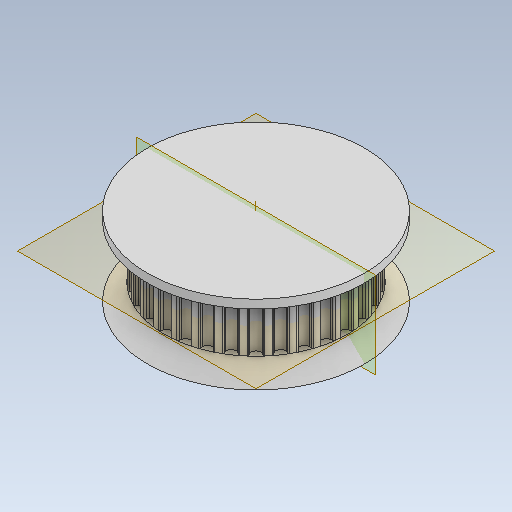
# Autodesk Inventor part: Riemenscheibe  GT2 32 Zähne mit kegel
Saved by Autodesk Inventor 2026.4 (Build 304435030, 435C)
## iProperties
Created: 2026-11-11
Part Number: Riemenscheibe  GT2 32 Zähne mit kegel
Material: Generisch
Document SubType Name: Modeling
Designer: weira
Density: 1 g/cm^3
Appearance: Vorgabe
Author: weira
Autodesk Inventor part; units mm, degrees
ref_plane "YZ Plane" through (0, 0, 0) normal (1, 0, 0) x (0, 1, 0)
sketch "Skizze1" plane through (0, 0, 0) normal (0, 0, 1) x (1, 0, 0)
  circle A0 centre (0, 0) radius 9.93
  arc A1 (-0.5239, 10.2923) -> (0.5239, 10.2923) centre (0, 10.49) ccw
  circle A2 centre (0, 0) radius 10.68
  arc A3 (0.4927, 10.2239) -> (0.5889, 10.5298) centre (-0.4, 10.6725) ccw
  arc A4 (-0.5889, 10.5298) -> (-0.5239, 10.2923) centre (0.4, 10.6725) ccw
  arc A5 (-0.5889, 10.5298) -> (-0.7421, 10.6542) centre (-0.7367, 10.5043) ccw
  line L0 (0, 10.49) -> (0, 10.844)
  arc A6 (0.7421, 10.6542) -> (0.5889, 10.5298) centre (0.7367, 10.5043) ccw
  arc A7 (-2.5218, 9.9923) -> (-1.4941, 10.1967) centre (-2.0465, 10.2884) ccw
  arc A8 (-1.5113, 10.1235) -> (-1.4767, 10.4423) centre (-2.4744, 10.3894) ccw
  arc A9 (-2.6318, 10.2126) -> (-2.5218, 9.9923) centre (-1.6898, 10.5455) ccw
  arc A10 (-2.6318, 10.2126) -> (-2.8064, 10.3047) centre (-2.7718, 10.1587) ccw
  arc A11 (-1.3507, 10.5942) -> (-1.4767, 10.4423) centre (-1.3268, 10.4462) ccw
  line L1 (-2.0465, 10.2884) -> (-2.1156, 10.6356)
  arc A12 (-4.4227, 9.3083) -> (-3.4546, 9.7093) centre (-4.0143, 9.6915) ccw
  arc A13 (-3.4573, 9.6342) -> (-3.4855, 9.9536) centre (-4.4537, 9.707) ccw
  arc A14 (-4.5736, 9.5029) -> (-4.4227, 9.3083) centre (-3.7146, 10.0132) ccw
  arc A15 (-4.5736, 9.5029) -> (-4.7628, 9.5592) centre (-4.7004, 9.4228) ccw
  arc A16 (-3.3916, 10.1272) -> (-3.4855, 9.9536) centre (-3.3392, 9.9866) ccw
  line L2 (-4.0143, 9.6915) -> (-4.1498, 10.0185)
  arc A17 (-6.1537, 8.2666) -> (-5.2824, 8.8488) centre (-5.8279, 8.7221) ccw
  arc A18 (-5.2704, 8.7746) -> (-5.3604, 9.0823) centre (-6.2619, 8.6516) ccw
  arc A19 (-6.3397, 8.428) -> (-6.1537, 8.2666) centre (-5.5967, 9.0961) ccw
  arc A20 (-6.3397, 8.428) -> (-6.5362, 8.4463) centre (-6.4484, 8.3247) ccw
  arc A21 (-5.3021, 9.2709) -> (-5.3604, 9.0823) centre (-5.2233, 9.1433) ccw
  line L3 (-5.8279, 8.7221) -> (-6.0246, 9.0164)
  arc A22 (-7.6482, 6.9073) -> (-6.9073, 7.6482) centre (-7.4176, 7.4176) ccw
  arc A23 (-6.881, 7.5778) -> (-7.0293, 7.8621) centre (-7.8294, 7.2638) ccw
  arc A24 (-7.8621, 7.0293) -> (-7.6482, 6.9073) centre (-7.2638, 7.8294) ccw
  arc A25 (-7.8621, 7.0293) -> (-8.0584, 7.0089) centre (-7.9486, 6.9067) ccw
  arc A26 (-7.0089, 8.0584) -> (-7.0293, 7.8621) centre (-6.9067, 7.9486) ccw
  line L4 (-7.4176, 7.4176) -> (-7.6678, 7.6678)
  arc A27 (-8.8488, 5.2824) -> (-8.2666, 6.1537) centre (-8.7221, 5.8279) ccw
  arc A28 (-8.2271, 6.0897) -> (-8.428, 6.3397) centre (-9.0961, 5.5967) ccw
  arc A29 (-9.0823, 5.3604) -> (-8.8488, 5.2824) centre (-8.6516, 6.2619) ccw
  arc A30 (-9.0823, 5.3604) -> (-9.2709, 5.3021) centre (-9.1433, 5.2233) ccw
  arc A31 (-8.4463, 6.5362) -> (-8.428, 6.3397) centre (-8.3247, 6.4484) ccw
  line L5 (-8.7221, 5.8279) -> (-9.0164, 6.0246)
  arc A32 (-9.7093, 3.4546) -> (-9.3083, 4.4227) centre (-9.6915, 4.0143) ccw
  arc A33 (-9.2571, 4.3677) -> (-9.5029, 4.5736) centre (-10.0132, 3.7146) ccw
  arc A34 (-9.9536, 3.4855) -> (-9.7093, 3.4546) centre (-9.707, 4.4537) ccw
  arc A35 (-9.9536, 3.4855) -> (-10.1272, 3.3916) centre (-9.9866, 3.3392) ccw
  arc A36 (-9.5592, 4.7628) -> (-9.5029, 4.5736) centre (-9.4228, 4.7004) ccw
  line L6 (-9.6915, 4.0143) -> (-10.0185, 4.1498)
  arc A37 (-10.1967, 1.4941) -> (-9.9923, 2.5218) centre (-10.2884, 2.0465) ccw
  arc A38 (-9.9313, 2.4778) -> (-10.2126, 2.6318) centre (-10.5455, 1.6898) ccw
  arc A39 (-10.4423, 1.4767) -> (-10.1967, 1.4941) centre (-10.3894, 2.4744) ccw
  arc A40 (-10.4423, 1.4767) -> (-10.5942, 1.3507) centre (-10.4462, 1.3268) ccw
  arc A41 (-10.3047, 2.8064) -> (-10.2126, 2.6318) centre (-10.1587, 2.7718) ccw
  line L7 (-10.2884, 2.0465) -> (-10.6356, 2.1156)
  arc A42 (-10.2923, -0.5239) -> (-10.2923, 0.5239) centre (-10.49, 0) ccw
  arc A43 (-10.2239, 0.4927) -> (-10.5298, 0.5889) centre (-10.6725, -0.4) ccw
  arc A44 (-10.5298, -0.5889) -> (-10.2923, -0.5239) centre (-10.6725, 0.4) ccw
  arc A45 (-10.5298, -0.5889) -> (-10.6542, -0.7421) centre (-10.5043, -0.7367) ccw
  arc A46 (-10.6542, 0.7421) -> (-10.5298, 0.5889) centre (-10.5043, 0.7367) ccw
  line L8 (-10.49, 0) -> (-10.844, 0)
  arc A47 (-9.9923, -2.5218) -> (-10.1967, -1.4941) centre (-10.2884, -2.0465) ccw
  arc A48 (-10.1235, -1.5113) -> (-10.4423, -1.4767) centre (-10.3894, -2.4744) ccw
  arc A49 (-10.2126, -2.6318) -> (-9.9923, -2.5218) centre (-10.5455, -1.6898) ccw
  arc A50 (-10.2126, -2.6318) -> (-10.3047, -2.8064) centre (-10.1587, -2.7718) ccw
  arc A51 (-10.5942, -1.3507) -> (-10.4423, -1.4767) centre (-10.4462, -1.3268) ccw
  line L9 (-10.2884, -2.0465) -> (-10.6356, -2.1156)
  arc A52 (-9.3083, -4.4227) -> (-9.7093, -3.4546) centre (-9.6915, -4.0143) ccw
  arc A53 (-9.6342, -3.4573) -> (-9.9536, -3.4855) centre (-9.707, -4.4537) ccw
  arc A54 (-9.5029, -4.5736) -> (-9.3083, -4.4227) centre (-10.0132, -3.7146) ccw
  arc A55 (-9.5029, -4.5736) -> (-9.5592, -4.7628) centre (-9.4228, -4.7004) ccw
  arc A56 (-10.1272, -3.3916) -> (-9.9536, -3.4855) centre (-9.9866, -3.3392) ccw
  line L10 (-9.6915, -4.0143) -> (-10.0185, -4.1498)
  arc A57 (-8.2666, -6.1537) -> (-8.8488, -5.2824) centre (-8.7221, -5.8279) ccw
  arc A58 (-8.7746, -5.2704) -> (-9.0823, -5.3604) centre (-8.6516, -6.2619) ccw
  arc A59 (-8.428, -6.3397) -> (-8.2666, -6.1537) centre (-9.0961, -5.5967) ccw
  arc A60 (-8.428, -6.3397) -> (-8.4463, -6.5362) centre (-8.3247, -6.4484) ccw
  arc A61 (-9.2709, -5.3021) -> (-9.0823, -5.3604) centre (-9.1433, -5.2233) ccw
  line L11 (-8.7221, -5.8279) -> (-9.0164, -6.0246)
  arc A62 (-6.9073, -7.6482) -> (-7.6482, -6.9073) centre (-7.4176, -7.4176) ccw
  arc A63 (-7.5778, -6.881) -> (-7.8621, -7.0293) centre (-7.2638, -7.8294) ccw
  arc A64 (-7.0293, -7.8621) -> (-6.9073, -7.6482) centre (-7.8294, -7.2638) ccw
  arc A65 (-7.0293, -7.8621) -> (-7.0089, -8.0584) centre (-6.9067, -7.9486) ccw
  arc A66 (-8.0584, -7.0089) -> (-7.8621, -7.0293) centre (-7.9486, -6.9067) ccw
  line L12 (-7.4176, -7.4176) -> (-7.6678, -7.6678)
  arc A67 (-5.2824, -8.8488) -> (-6.1537, -8.2666) centre (-5.8279, -8.7221) ccw
  arc A68 (-6.0897, -8.2271) -> (-6.3397, -8.428) centre (-5.5967, -9.0961) ccw
  arc A69 (-5.3604, -9.0823) -> (-5.2824, -8.8488) centre (-6.2619, -8.6516) ccw
  arc A70 (-5.3604, -9.0823) -> (-5.3021, -9.2709) centre (-5.2233, -9.1433) ccw
  arc A71 (-6.5362, -8.4463) -> (-6.3397, -8.428) centre (-6.4484, -8.3247) ccw
  line L13 (-5.8279, -8.7221) -> (-6.0246, -9.0164)
  arc A72 (-3.4546, -9.7093) -> (-4.4227, -9.3083) centre (-4.0143, -9.6915) ccw
  arc A73 (-4.3677, -9.2571) -> (-4.5736, -9.5029) centre (-3.7146, -10.0132) ccw
  arc A74 (-3.4855, -9.9536) -> (-3.4546, -9.7093) centre (-4.4537, -9.707) ccw
  arc A75 (-3.4855, -9.9536) -> (-3.3916, -10.1272) centre (-3.3392, -9.9866) ccw
  arc A76 (-4.7628, -9.5592) -> (-4.5736, -9.5029) centre (-4.7004, -9.4228) ccw
  line L14 (-4.0143, -9.6915) -> (-4.1498, -10.0185)
  arc A77 (-1.4941, -10.1967) -> (-2.5218, -9.9923) centre (-2.0465, -10.2884) ccw
  arc A78 (-2.4778, -9.9313) -> (-2.6318, -10.2126) centre (-1.6898, -10.5455) ccw
  arc A79 (-1.4767, -10.4423) -> (-1.4941, -10.1967) centre (-2.4744, -10.3894) ccw
  arc A80 (-1.4767, -10.4423) -> (-1.3507, -10.5942) centre (-1.3268, -10.4462) ccw
  arc A81 (-2.8064, -10.3047) -> (-2.6318, -10.2126) centre (-2.7718, -10.1587) ccw
  line L15 (-2.0465, -10.2884) -> (-2.1156, -10.6356)
  arc A82 (0.5239, -10.2923) -> (-0.5239, -10.2923) centre (0, -10.49) ccw
  arc A83 (-0.4927, -10.2239) -> (-0.5889, -10.5298) centre (0.4, -10.6725) ccw
  arc A84 (0.5889, -10.5298) -> (0.5239, -10.2923) centre (-0.4, -10.6725) ccw
  arc A85 (0.5889, -10.5298) -> (0.7421, -10.6542) centre (0.7367, -10.5043) ccw
  arc A86 (-0.7421, -10.6542) -> (-0.5889, -10.5298) centre (-0.7367, -10.5043) ccw
  line L16 (0, -10.49) -> (0, -10.844)
  arc A87 (2.5218, -9.9923) -> (1.4941, -10.1967) centre (2.0465, -10.2884) ccw
  arc A88 (1.5113, -10.1235) -> (1.4767, -10.4423) centre (2.4744, -10.3894) ccw
  arc A89 (2.6318, -10.2126) -> (2.5218, -9.9923) centre (1.6898, -10.5455) ccw
  arc A90 (2.6318, -10.2126) -> (2.8064, -10.3047) centre (2.7718, -10.1587) ccw
  arc A91 (1.3507, -10.5942) -> (1.4767, -10.4423) centre (1.3268, -10.4462) ccw
  line L17 (2.0465, -10.2884) -> (2.1156, -10.6356)
  arc A92 (4.4227, -9.3083) -> (3.4546, -9.7093) centre (4.0143, -9.6915) ccw
  arc A93 (3.4573, -9.6342) -> (3.4855, -9.9536) centre (4.4537, -9.707) ccw
  arc A94 (4.5736, -9.5029) -> (4.4227, -9.3083) centre (3.7146, -10.0132) ccw
  arc A95 (4.5736, -9.5029) -> (4.7628, -9.5592) centre (4.7004, -9.4228) ccw
  arc A96 (3.3916, -10.1272) -> (3.4855, -9.9536) centre (3.3392, -9.9866) ccw
  line L18 (4.0143, -9.6915) -> (4.1498, -10.0185)
  arc A97 (6.1537, -8.2666) -> (5.2824, -8.8488) centre (5.8279, -8.7221) ccw
  arc A98 (5.2704, -8.7746) -> (5.3604, -9.0823) centre (6.2619, -8.6516) ccw
  arc A99 (6.3397, -8.428) -> (6.1537, -8.2666) centre (5.5967, -9.0961) ccw
  arc A100 (6.3397, -8.428) -> (6.5362, -8.4463) centre (6.4484, -8.3247) ccw
  arc A101 (5.3021, -9.2709) -> (5.3604, -9.0823) centre (5.2233, -9.1433) ccw
  line L19 (5.8279, -8.7221) -> (6.0246, -9.0164)
  arc A102 (7.6482, -6.9073) -> (6.9073, -7.6482) centre (7.4176, -7.4176) ccw
  arc A103 (6.881, -7.5778) -> (7.0293, -7.8621) centre (7.8294, -7.2638) ccw
  arc A104 (7.8621, -7.0293) -> (7.6482, -6.9073) centre (7.2638, -7.8294) ccw
  arc A105 (7.8621, -7.0293) -> (8.0584, -7.0089) centre (7.9486, -6.9067) ccw
  arc A106 (7.0089, -8.0584) -> (7.0293, -7.8621) centre (6.9067, -7.9486) ccw
  line L20 (7.4176, -7.4176) -> (7.6678, -7.6678)
  arc A107 (8.8488, -5.2824) -> (8.2666, -6.1537) centre (8.7221, -5.8279) ccw
  arc A108 (8.2271, -6.0897) -> (8.428, -6.3397) centre (9.0961, -5.5967) ccw
  arc A109 (9.0823, -5.3604) -> (8.8488, -5.2824) centre (8.6516, -6.2619) ccw
  arc A110 (9.0823, -5.3604) -> (9.2709, -5.3021) centre (9.1433, -5.2233) ccw
  arc A111 (8.4463, -6.5362) -> (8.428, -6.3397) centre (8.3247, -6.4484) ccw
  line L21 (8.7221, -5.8279) -> (9.0164, -6.0246)
  arc A112 (9.7093, -3.4546) -> (9.3083, -4.4227) centre (9.6915, -4.0143) ccw
  arc A113 (9.2571, -4.3677) -> (9.5029, -4.5736) centre (10.0132, -3.7146) ccw
  arc A114 (9.9536, -3.4855) -> (9.7093, -3.4546) centre (9.707, -4.4537) ccw
  arc A115 (9.9536, -3.4855) -> (10.1272, -3.3916) centre (9.9866, -3.3392) ccw
  arc A116 (9.5592, -4.7628) -> (9.5029, -4.5736) centre (9.4228, -4.7004) ccw
  line L22 (9.6915, -4.0143) -> (10.0185, -4.1498)
  arc A117 (10.1967, -1.4941) -> (9.9923, -2.5218) centre (10.2884, -2.0465) ccw
  arc A118 (9.9313, -2.4778) -> (10.2126, -2.6318) centre (10.5455, -1.6898) ccw
  arc A119 (10.4423, -1.4767) -> (10.1967, -1.4941) centre (10.3894, -2.4744) ccw
  arc A120 (10.4423, -1.4767) -> (10.5942, -1.3507) centre (10.4462, -1.3268) ccw
  arc A121 (10.3047, -2.8064) -> (10.2126, -2.6318) centre (10.1587, -2.7718) ccw
  line L23 (10.2884, -2.0465) -> (10.6356, -2.1156)
  arc A122 (10.2923, 0.5239) -> (10.2923, -0.5239) centre (10.49, 0) ccw
  arc A123 (10.2239, -0.4927) -> (10.5298, -0.5889) centre (10.6725, 0.4) ccw
  arc A124 (10.5298, 0.5889) -> (10.2923, 0.5239) centre (10.6725, -0.4) ccw
  arc A125 (10.5298, 0.5889) -> (10.6542, 0.7421) centre (10.5043, 0.7367) ccw
  arc A126 (10.6542, -0.7421) -> (10.5298, -0.5889) centre (10.5043, -0.7367) ccw
  line L24 (10.49, 0) -> (10.844, 0)
  arc A127 (9.9923, 2.5218) -> (10.1967, 1.4941) centre (10.2884, 2.0465) ccw
  arc A128 (10.1235, 1.5113) -> (10.4423, 1.4767) centre (10.3894, 2.4744) ccw
  arc A129 (10.2126, 2.6318) -> (9.9923, 2.5218) centre (10.5455, 1.6898) ccw
  arc A130 (10.2126, 2.6318) -> (10.3047, 2.8064) centre (10.1587, 2.7718) ccw
  arc A131 (10.5942, 1.3507) -> (10.4423, 1.4767) centre (10.4462, 1.3268) ccw
  line L25 (10.2884, 2.0465) -> (10.6356, 2.1156)
  arc A132 (9.3083, 4.4227) -> (9.7093, 3.4546) centre (9.6915, 4.0143) ccw
  arc A133 (9.6342, 3.4573) -> (9.9536, 3.4855) centre (9.707, 4.4537) ccw
  arc A134 (9.5029, 4.5736) -> (9.3083, 4.4227) centre (10.0132, 3.7146) ccw
  arc A135 (9.5029, 4.5736) -> (9.5592, 4.7628) centre (9.4228, 4.7004) ccw
  arc A136 (10.1272, 3.3916) -> (9.9536, 3.4855) centre (9.9866, 3.3392) ccw
  line L26 (9.6915, 4.0143) -> (10.0185, 4.1498)
  arc A137 (8.2666, 6.1537) -> (8.8488, 5.2824) centre (8.7221, 5.8279) ccw
  arc A138 (8.7746, 5.2704) -> (9.0823, 5.3604) centre (8.6516, 6.2619) ccw
  arc A139 (8.428, 6.3397) -> (8.2666, 6.1537) centre (9.0961, 5.5967) ccw
  arc A140 (8.428, 6.3397) -> (8.4463, 6.5362) centre (8.3247, 6.4484) ccw
  arc A141 (9.2709, 5.3021) -> (9.0823, 5.3604) centre (9.1433, 5.2233) ccw
  line L27 (8.7221, 5.8279) -> (9.0164, 6.0246)
  arc A142 (6.9073, 7.6482) -> (7.6482, 6.9073) centre (7.4176, 7.4176) ccw
  arc A143 (7.5778, 6.881) -> (7.8621, 7.0293) centre (7.2638, 7.8294) ccw
  arc A144 (7.0293, 7.8621) -> (6.9073, 7.6482) centre (7.8294, 7.2638) ccw
  arc A145 (7.0293, 7.8621) -> (7.0089, 8.0584) centre (6.9067, 7.9486) ccw
  arc A146 (8.0584, 7.0089) -> (7.8621, 7.0293) centre (7.9486, 6.9067) ccw
  line L28 (7.4176, 7.4176) -> (7.6678, 7.6678)
  arc A147 (5.2824, 8.8488) -> (6.1537, 8.2666) centre (5.8279, 8.7221) ccw
  arc A148 (6.0897, 8.2271) -> (6.3397, 8.428) centre (5.5967, 9.0961) ccw
  arc A149 (5.3604, 9.0823) -> (5.2824, 8.8488) centre (6.2619, 8.6516) ccw
  arc A150 (5.3604, 9.0823) -> (5.3021, 9.2709) centre (5.2233, 9.1433) ccw
  arc A151 (6.5362, 8.4463) -> (6.3397, 8.428) centre (6.4484, 8.3247) ccw
  line L29 (5.8279, 8.7221) -> (6.0246, 9.0164)
  arc A152 (3.4546, 9.7093) -> (4.4227, 9.3083) centre (4.0143, 9.6915) ccw
  arc A153 (4.3677, 9.2571) -> (4.5736, 9.5029) centre (3.7146, 10.0132) ccw
  arc A154 (3.4855, 9.9536) -> (3.4546, 9.7093) centre (4.4537, 9.707) ccw
  arc A155 (3.4855, 9.9536) -> (3.3916, 10.1272) centre (3.3392, 9.9866) ccw
  arc A156 (4.7628, 9.5592) -> (4.5736, 9.5029) centre (4.7004, 9.4228) ccw
  line L30 (4.0143, 9.6915) -> (4.1498, 10.0185)
  arc A157 (1.4941, 10.1967) -> (2.5218, 9.9923) centre (2.0465, 10.2884) ccw
  arc A158 (2.4778, 9.9313) -> (2.6318, 10.2126) centre (1.6898, 10.5455) ccw
  arc A159 (1.4767, 10.4423) -> (1.4941, 10.1967) centre (2.4744, 10.3894) ccw
  arc A160 (1.4767, 10.4423) -> (1.3507, 10.5942) centre (1.3268, 10.4462) ccw
  arc A161 (2.8064, 10.3047) -> (2.6318, 10.2126) centre (2.7718, 10.1587) ccw
  line L31 (2.0465, 10.2884) -> (2.1156, 10.6356)
  point P0 (-0.5996, 10.6632)
  point P1 (0.5996, 10.6632)
  point P2 (-2.6684, 10.3413)
  point P3 (-1.4922, 10.5752)
  point P4 (-4.6346, 9.622)
  point P5 (-3.5267, 10.0809)
  point P6 (-6.4227, 8.533)
  point P7 (-5.4256, 9.1992)
  point P8 (-7.964, 7.116)
  point P9 (-7.116, 7.964)
  point P10 (-9.1992, 5.4256)
  point P11 (-8.533, 6.4227)
  point P12 (-10.0809, 3.5267)
  point P13 (-9.622, 4.6346)
  point P14 (-10.5752, 1.4922)
  point P15 (-10.3413, 2.6684)
  point P16 (-10.6632, -0.5996)
  point P17 (-10.6632, 0.5996)
  point P18 (-10.3413, -2.6684)
  point P19 (-10.5752, -1.4922)
  point P20 (-9.622, -4.6346)
  point P21 (-10.0809, -3.5267)
  point P22 (-8.533, -6.4227)
  point P23 (-9.1992, -5.4256)
  point P24 (-7.116, -7.964)
  point P25 (-7.964, -7.116)
  point P26 (-5.4256, -9.1992)
  point P27 (-6.4227, -8.533)
  point P28 (-3.5267, -10.0809)
  point P29 (-4.6346, -9.622)
  point P30 (-1.4922, -10.5752)
  point P31 (-2.6684, -10.3413)
  point P32 (0.5996, -10.6632)
  point P33 (-0.5996, -10.6632)
  point P34 (2.6684, -10.3413)
  point P35 (1.4922, -10.5752)
  point P36 (4.6346, -9.622)
  point P37 (3.5267, -10.0809)
  point P38 (6.4227, -8.533)
  point P39 (5.4256, -9.1992)
  point P40 (7.964, -7.116)
  point P41 (7.116, -7.964)
  point P42 (9.1992, -5.4256)
  point P43 (8.533, -6.4227)
  point P44 (10.0809, -3.5267)
  point P45 (9.622, -4.6346)
  point P46 (10.5752, -1.4922)
  point P47 (10.3413, -2.6684)
  point P48 (10.6632, 0.5996)
  point P49 (10.6632, -0.5996)
  point P50 (10.3413, 2.6684)
  point P51 (10.5752, 1.4922)
  point P52 (9.622, 4.6346)
  point P53 (10.0809, 3.5267)
  point P54 (8.533, 6.4227)
  point P55 (9.1992, 5.4256)
  point P56 (7.116, 7.964)
  point P57 (7.964, 7.116)
  point P58 (5.4256, 9.1992)
  point P59 (6.4227, 8.533)
  point P60 (3.5267, 10.0809)
  point P61 (4.6346, 9.622)
  point P62 (1.4922, 10.5752)
  point P63 (2.6684, 10.3413)
  point P64 (-6.5362, 8.4463)
  point P65 (-7.0089, 8.0584)
  point P66 (-8.0584, 7.0089)
  point P67 (-8.4463, 6.5362)
  point P68 (-9.2709, 5.3021)
  point P69 (-9.5592, 4.7628)
  point P70 (-10.1272, 3.3916)
  point P71 (-10.3047, 2.8064)
  point P72 (-10.5942, 1.3507)
  point P73 (-10.6542, 0.7421)
  point P74 (-10.6542, -0.7421)
  point P75 (-10.5942, -1.3507)
  point P76 (-10.3047, -2.8064)
  point P77 (-10.1272, -3.3916)
  point P78 (-9.5592, -4.7628)
  point P79 (-9.2709, -5.3021)
  point P80 (-8.4463, -6.5362)
  point P81 (-8.0584, -7.0089)
  point P82 (-7.0089, -8.0584)
  point P83 (-6.5362, -8.4463)
  point P84 (-5.3021, -9.2709)
  point P85 (-4.7628, -9.5592)
  point P86 (-3.3916, -10.1272)
  point P87 (-2.8064, -10.3047)
  point P88 (-1.3507, -10.5942)
  point P89 (-0.7421, -10.6542)
  point P90 (0.7421, -10.6542)
  point P91 (1.3507, -10.5942)
  point P92 (2.8064, -10.3047)
  point P93 (3.3916, -10.1272)
  point P94 (4.7628, -9.5592)
  point P95 (5.3021, -9.2709)
  point P96 (6.5362, -8.4463)
  point P97 (7.0089, -8.0584)
  point P98 (8.0584, -7.0089)
  point P99 (8.4463, -6.5362)
  point P100 (9.2709, -5.3021)
  point P101 (9.5592, -4.7628)
  point P102 (10.1272, -3.3916)
  point P103 (10.3047, -2.8064)
  point P104 (10.5942, -1.3507)
  point P105 (10.6542, -0.7421)
  point P106 (10.6542, 0.7421)
  point P107 (10.5942, 1.3507)
  point P108 (10.3047, 2.8064)
  point P109 (10.1272, 3.3916)
  point P110 (9.5592, 4.7628)
  point P111 (9.2709, 5.3021)
  point P112 (8.4463, 6.5362)
  point P113 (8.0584, 7.0089)
  point P114 (7.0089, 8.0584)
  point P115 (6.5362, 8.4463)
  point P116 (5.3021, 9.2709)
  point P117 (4.7628, 9.5592)
  point P118 (3.3916, 10.1272)
  point P119 (2.8064, 10.3047)
  point P120 (1.3507, 10.5942)
  point P121 (-1.3507, 10.5942)
  point P122 (-2.8064, 10.3047)
  point P123 (-3.3916, 10.1272)
  point P124 (-4.7628, 9.5592)
  point P125 (-5.3021, 9.2709)
  dimension "d7" = 21.36
  dimension "d0" = 19.86
  dimension "d6" = 1.12
  dimension "d8" = 0.4
  dimension "d9" = 0
  dimension "d10" = 0.4
  dimension "d11" = 0.15
  dimension "d14" = 360
  constraints: 384 point on circle, 161 centre point, 66 coincident, 64 end point, 4 symmetric about line, 1 tangent, 1 vertical, 744 other
  measures "d0" diameter of A0
  measures "d6" diameter of A1
  measures "d8" horizontal distance of L0.start point (-0.4, 10.673)
  measures "d9" horizontal distance of point (0, 0) L0.start
  measures "d10" horizontal distance of L0.start point (0.4, 10.673)
  measures "d11" radius of A5
extrude "Extrusion1" add sketch "Skizze1" along normal mid plane 6.2 contours A0 | A122 A123 A126 A2 A120 A119 A117 A0 | A0 A127 A128 A131 A2 A125 A124 A122 | A0 A132 A133 A136 A2 A130 A129 A127 | A117 A118 A121 A2 A115 A114 A112 A0 | A0 A137 A138 A141 A2 A135 A134 A132 | A112 A113 A116 A2 A110 A109 A107 A0 | A0 A142 A143 A146 A2 A140 A139 A137 | A107 A108 A111 A2 A105 A104 A102 A0 | A0 A147 A148 A151 A2 A145 A144 A142 | A102 A103 A106 A2 A100 A99 A97 A0 | A0 A152 A153 A156 A2 A150 A149 A147 | A97 A98 A101 A2 A95 A94 A92 A0 | A0 A157 A158 A161 A2 A155 A154 A152 | A92 A93 A96 A2 A90 A89 A87 A0 | A0 A1 A3 A6 A2 A160 A159 A157 | A87 A88 A91 A2 A85 A84 A82 A0 | A0 A7 A8 A11 A2 A5 A4 A1 | A82 A83 A86 A2 A80 A79 A77 A0 | A0 A12 A13 A16 A2 A10 A9 A7 | A77 A78 A81 A2 A75 A74 A72 A0 | A0 A17 A18 A21 A2 A15 A14 A12 | A72 A73 A76 A2 A70 A69 A67 A0 | A0 A22 A23 A26 A2 A20 A19 A17 | A67 A68 A71 A2 A65 A64 A62 A0 | A0 A27 A28 A31 A2 A25 A24 A22 | A62 A63 A66 A2 A60 A59 A57 A0 | A0 A32 A33 A36 A2 A30 A29 A27 | A57 A58 A61 A2 A55 A54 A52 A0 | A0 A37 A38 A41 A2 A35 A34 A32 | A52 A53 A56 A2 A50 A49 A47 A0 | A0 A42 A43 A46 A2 A40 A39 A37 | A47 A48 A51 A2 A45 A44 A42 A0
sketch "Skizze3" plane through (0, 0, 3.1) normal (0, 0, 1) x (1, 0, 0)
  circle A0 centre (0, 0) radius 10.6817
  circle A1 centre (0, 0) radius 12.6817
  dimension "d18" = 2
  constraints: 2 centre point, 2 coincident
  measures "d18" radial gap between concentric circles of A0 A1
extrude "Extrusion2" add sketch "Skizze3" along normal blind 1 contours A0 | A1
sketch "Skizze5" plane through (0, 0, 0) normal (0, 1, 0) x (-1, 0, 0)
  line L0 (12.6817, 3.1) -> (-12.6817, 3.1) projected
  line L1 (2.5218, 3.1) -> (2.6318, 3.1) projected
  line L2 (2.6318, 3.1) -> (2.8064, 3.1) projected
  line L3 (2.8064, 3.1) -> (3.3916, 3.1) projected
  line L4 (3.3916, 3.1) -> (3.4855, 3.1) projected
  line L5 (3.4855, 3.1) -> (3.4546, 3.1) projected
  line L6 (3.4546, 3.1) -> (4.4227, 3.1) projected
  line L7 (4.4227, 3.1) -> (4.5736, 3.1) projected
  line L8 (4.5736, 3.1) -> (4.7628, 3.1) projected
  line L9 (4.7628, 3.1) -> (5.3021, 3.1) projected
  line L10 (5.3021, 3.1) -> (5.3604, 3.1) projected
  line L11 (5.3604, 3.1) -> (5.2824, 3.1) projected
  line L12 (5.2824, 3.1) -> (6.1537, 3.1) projected
  line L13 (6.1537, 3.1) -> (6.3397, 3.1) projected
  line L14 (6.3397, 3.1) -> (6.5362, 3.1) projected
  line L15 (6.5362, 3.1) -> (7.0089, 3.1) projected
  line L16 (7.0089, 3.1) -> (7.0293, 3.1) projected
  line L17 (7.0293, 3.1) -> (6.9073, 3.1) projected
  line L18 (6.9073, 3.1) -> (7.6482, 3.1) projected
  line L19 (7.6482, 3.1) -> (7.8621, 3.1) projected
  line L20 (7.8621, 3.1) -> (8.0584, 3.1) projected
  line L21 (8.0584, 3.1) -> (8.4463, 3.1) projected
  line L22 (8.4463, 3.1) -> (8.428, 3.1) projected
  line L23 (8.428, 3.1) -> (8.2666, 3.1) projected
  line L24 (8.2666, 3.1) -> (8.8488, 3.1) projected
  line L25 (8.8488, 3.1) -> (9.0823, 3.1) projected
  line L26 (9.0823, 3.1) -> (9.2709, 3.1) projected
  line L27 (9.2709, 3.1) -> (9.5592, 3.1) projected
  line L28 (9.5592, 3.1) -> (9.5029, 3.1) projected
  line L29 (9.5029, 3.1) -> (9.3083, 3.1) projected
  line L30 (9.3083, 3.1) -> (9.7093, 3.1) projected
  line L31 (9.7093, 3.1) -> (9.9536, 3.1) projected
  line L32 (9.9536, 3.1) -> (10.1272, 3.1) projected
  line L33 (10.1272, 3.1) -> (10.3047, 3.1) projected
  line L34 (10.3047, 3.1) -> (10.2126, 3.1) projected
  line L35 (10.2126, 3.1) -> (9.9923, 3.1) projected
  line L36 (9.9923, 3.1) -> (10.1967, 3.1) projected
  line L37 (10.1967, 3.1) -> (10.4423, 3.1) projected
  line L38 (10.4423, 3.1) -> (10.5942, 3.1) projected
  line L39 (10.5942, 3.1) -> (10.6542, 3.1) projected
  line L40 (10.6542, 3.1) -> (10.5298, 3.1) projected
  line L41 (10.5298, 3.1) -> (10.2923, 3.1) projected
  line L42 (10.2923, 3.1) -> (10.2923, 3.1) projected
  line L43 (10.2923, 3.1) -> (10.5298, 3.1) projected
  line L44 (10.5298, 3.1) -> (10.6542, 3.1) projected
  line L45 (10.6542, 3.1) -> (10.5942, 3.1) projected
  line L46 (10.5942, 3.1) -> (10.4423, 3.1) projected
  line L47 (10.4423, 3.1) -> (10.1967, 3.1) projected
  line L48 (10.1967, 3.1) -> (9.9923, 3.1) projected
  line L49 (9.9923, 3.1) -> (10.2126, 3.1) projected
  line L50 (10.2126, 3.1) -> (10.3047, 3.1) projected
  line L51 (10.3047, 3.1) -> (10.1272, 3.1) projected
  line L52 (10.1272, 3.1) -> (9.9536, 3.1) projected
  line L53 (9.9536, 3.1) -> (9.7093, 3.1) projected
  line L54 (9.7093, 3.1) -> (9.3083, 3.1) projected
  line L55 (9.3083, 3.1) -> (9.5029, 3.1) projected
  line L56 (9.5029, 3.1) -> (9.5592, 3.1) projected
  line L57 (9.5592, 3.1) -> (9.2709, 3.1) projected
  line L58 (9.2709, 3.1) -> (9.0823, 3.1) projected
  line L59 (9.0823, 3.1) -> (8.8488, 3.1) projected
  line L60 (8.8488, 3.1) -> (8.2666, 3.1) projected
  line L61 (8.2666, 3.1) -> (8.428, 3.1) projected
  line L62 (8.428, 3.1) -> (8.4463, 3.1) projected
  line L63 (8.4463, 3.1) -> (8.0584, 3.1) projected
  line L64 (8.0584, 3.1) -> (7.8621, 3.1) projected
  line L65 (7.8621, 3.1) -> (7.6482, 3.1) projected
  line L66 (7.6482, 3.1) -> (6.9073, 3.1) projected
  line L67 (6.9073, 3.1) -> (7.0293, 3.1) projected
  line L68 (7.0293, 3.1) -> (7.0089, 3.1) projected
  line L69 (7.0089, 3.1) -> (6.5362, 3.1) projected
  line L70 (6.5362, 3.1) -> (6.3397, 3.1) projected
  line L71 (6.3397, 3.1) -> (6.1537, 3.1) projected
  line L72 (6.1537, 3.1) -> (5.2824, 3.1) projected
  line L73 (5.2824, 3.1) -> (5.3604, 3.1) projected
  line L74 (5.3604, 3.1) -> (5.3021, 3.1) projected
  line L75 (5.3021, 3.1) -> (4.7628, 3.1) projected
  line L76 (4.7628, 3.1) -> (4.5736, 3.1) projected
  line L77 (4.5736, 3.1) -> (4.4227, 3.1) projected
  line L78 (4.4227, 3.1) -> (3.4546, 3.1) projected
  line L79 (3.4546, 3.1) -> (3.4855, 3.1) projected
  line L80 (3.4855, 3.1) -> (3.3916, 3.1) projected
  line L81 (3.3916, 3.1) -> (2.8064, 3.1) projected
  line L82 (2.8064, 3.1) -> (2.6318, 3.1) projected
  line L83 (2.6318, 3.1) -> (2.5218, 3.1) projected
  line L84 (2.5218, 3.1) -> (1.4941, 3.1) projected
  line L85 (1.4941, 3.1) -> (1.4767, 3.1) projected
  line L86 (1.4767, 3.1) -> (1.3507, 3.1) projected
  line L87 (1.3507, 3.1) -> (0.7421, 3.1) projected
  line L88 (0.7421, 3.1) -> (0.5889, 3.1) projected
  line L89 (0.5889, 3.1) -> (0.5239, 3.1) projected
  line L90 (0.5239, 3.1) -> (-0.5239, 3.1) projected
  line L91 (-0.5239, 3.1) -> (-0.5889, 3.1) projected
  line L92 (-0.5889, 3.1) -> (-0.7421, 3.1) projected
  line L93 (-0.7421, 3.1) -> (-1.3507, 3.1) projected
  line L94 (-1.3507, 3.1) -> (-1.4767, 3.1) projected
  line L95 (-1.4767, 3.1) -> (-1.4941, 3.1) projected
  line L96 (-1.4941, 3.1) -> (-2.5218, 3.1) projected
  line L97 (-2.5218, 3.1) -> (-2.6318, 3.1) projected
  line L98 (-2.6318, 3.1) -> (-2.8064, 3.1) projected
  line L99 (-2.8064, 3.1) -> (-3.3916, 3.1) projected
  line L100 (-3.3916, 3.1) -> (-3.4855, 3.1) projected
  line L101 (-3.4855, 3.1) -> (-3.4546, 3.1) projected
  line L102 (-3.4546, 3.1) -> (-4.4227, 3.1) projected
  line L103 (-4.4227, 3.1) -> (-4.5736, 3.1) projected
  line L104 (-4.5736, 3.1) -> (-4.7628, 3.1) projected
  line L105 (-4.7628, 3.1) -> (-5.3021, 3.1) projected
  line L106 (-5.3021, 3.1) -> (-5.3604, 3.1) projected
  line L107 (-5.3604, 3.1) -> (-5.2824, 3.1) projected
  line L108 (-5.2824, 3.1) -> (-6.1537, 3.1) projected
  line L109 (-6.1537, 3.1) -> (-6.3397, 3.1) projected
  line L110 (-6.3397, 3.1) -> (-6.5362, 3.1) projected
  line L111 (-6.5362, 3.1) -> (-7.0089, 3.1) projected
  line L112 (-7.0089, 3.1) -> (-7.0293, 3.1) projected
  line L113 (-7.0293, 3.1) -> (-6.9073, 3.1) projected
  line L114 (-6.9073, 3.1) -> (-7.6482, 3.1) projected
  line L115 (-7.6482, 3.1) -> (-7.8621, 3.1) projected
  line L116 (-7.8621, 3.1) -> (-8.0584, 3.1) projected
  line L117 (-8.0584, 3.1) -> (-8.4463, 3.1) projected
  line L118 (-8.4463, 3.1) -> (-8.428, 3.1) projected
  line L119 (-8.428, 3.1) -> (-8.2666, 3.1) projected
  line L120 (-8.2666, 3.1) -> (-8.8488, 3.1) projected
  line L121 (-8.8488, 3.1) -> (-9.0823, 3.1) projected
  line L122 (-9.0823, 3.1) -> (-9.2709, 3.1) projected
  line L123 (-9.2709, 3.1) -> (-9.5592, 3.1) projected
  line L124 (-9.5592, 3.1) -> (-9.5029, 3.1) projected
  line L125 (-9.5029, 3.1) -> (-9.3083, 3.1) projected
  line L126 (-9.3083, 3.1) -> (-9.7093, 3.1) projected
  line L127 (-9.7093, 3.1) -> (-9.9536, 3.1) projected
  line L128 (-9.9536, 3.1) -> (-10.1272, 3.1) projected
  line L129 (-10.1272, 3.1) -> (-10.3047, 3.1) projected
  line L130 (-10.3047, 3.1) -> (-10.2126, 3.1) projected
  line L131 (-10.2126, 3.1) -> (-9.9923, 3.1) projected
  line L132 (-9.9923, 3.1) -> (-10.1967, 3.1) projected
  line L133 (-10.1967, 3.1) -> (-10.4423, 3.1) projected
  line L134 (-10.4423, 3.1) -> (-10.5942, 3.1) projected
  line L135 (-10.5942, 3.1) -> (-10.6542, 3.1) projected
  line L136 (-10.6542, 3.1) -> (-10.5298, 3.1) projected
  line L137 (-10.5298, 3.1) -> (-10.2923, 3.1) projected
  line L138 (-10.2923, 3.1) -> (-10.2923, 3.1) projected
  line L139 (-10.2923, 3.1) -> (-10.5298, 3.1) projected
  line L140 (-10.5298, 3.1) -> (-10.6542, 3.1) projected
  line L141 (-10.6542, 3.1) -> (-10.5942, 3.1) projected
  line L142 (-10.5942, 3.1) -> (-10.4423, 3.1) projected
  line L143 (-10.4423, 3.1) -> (-10.1967, 3.1) projected
  line L144 (-10.1967, 3.1) -> (-9.9923, 3.1) projected
  line L145 (-9.9923, 3.1) -> (-10.2126, 3.1) projected
  line L146 (-10.2126, 3.1) -> (-10.3047, 3.1) projected
  line L147 (-10.3047, 3.1) -> (-10.1272, 3.1) projected
  line L148 (-10.1272, 3.1) -> (-9.9536, 3.1) projected
  line L149 (-9.9536, 3.1) -> (-9.7093, 3.1) projected
  line L150 (-9.7093, 3.1) -> (-9.3083, 3.1) projected
  line L151 (-9.3083, 3.1) -> (-9.5029, 3.1) projected
  line L152 (-9.5029, 3.1) -> (-9.5592, 3.1) projected
  line L153 (-9.5592, 3.1) -> (-9.2709, 3.1) projected
  line L154 (-9.2709, 3.1) -> (-9.0823, 3.1) projected
  line L155 (-9.0823, 3.1) -> (-8.8488, 3.1) projected
  line L156 (-8.8488, 3.1) -> (-8.2666, 3.1) projected
  line L157 (-8.2666, 3.1) -> (-8.428, 3.1) projected
  line L158 (-8.428, 3.1) -> (-8.4463, 3.1) projected
  line L159 (-8.4463, 3.1) -> (-8.0584, 3.1) projected
  line L160 (-8.0584, 3.1) -> (-7.8621, 3.1) projected
  line L161 (-7.8621, 3.1) -> (-7.6482, 3.1) projected
  line L162 (-7.6482, 3.1) -> (-6.9073, 3.1) projected
  line L163 (-6.9073, 3.1) -> (-7.0293, 3.1) projected
  line L164 (-7.0293, 3.1) -> (-7.0089, 3.1) projected
  line L165 (-7.0089, 3.1) -> (-6.5362, 3.1) projected
  line L166 (-6.5362, 3.1) -> (-6.3397, 3.1) projected
  line L167 (-6.3397, 3.1) -> (-6.1537, 3.1) projected
  line L168 (-6.1537, 3.1) -> (-5.2824, 3.1) projected
  line L169 (-5.2824, 3.1) -> (-5.3604, 3.1) projected
  line L170 (-5.3604, 3.1) -> (-5.3021, 3.1) projected
  line L171 (-5.3021, 3.1) -> (-4.7628, 3.1) projected
  line L172 (-4.7628, 3.1) -> (-4.5736, 3.1) projected
  line L173 (-4.5736, 3.1) -> (-4.4227, 3.1) projected
  line L174 (-4.4227, 3.1) -> (-3.4546, 3.1) projected
  line L175 (-3.4546, 3.1) -> (-3.4855, 3.1) projected
  line L176 (-3.4855, 3.1) -> (-3.3916, 3.1) projected
  line L177 (-3.3916, 3.1) -> (-2.8064, 3.1) projected
  line L178 (-2.8064, 3.1) -> (-2.6318, 3.1) projected
  line L179 (-2.6318, 3.1) -> (-2.5218, 3.1) projected
  line L180 (-2.5218, 3.1) -> (-1.4941, 3.1) projected
  line L181 (-1.4941, 3.1) -> (-1.4767, 3.1) projected
  line L182 (-1.4767, 3.1) -> (-1.3507, 3.1) projected
  line L183 (-1.3507, 3.1) -> (-0.7421, 3.1) projected
  line L184 (-0.7421, 3.1) -> (-0.5889, 3.1) projected
  line L185 (-0.5889, 3.1) -> (-0.5239, 3.1) projected
  line L186 (-0.5239, 3.1) -> (0.5239, 3.1) projected
  line L187 (0.5239, 3.1) -> (0.5889, 3.1) projected
  line L188 (0.5889, 3.1) -> (0.7421, 3.1) projected
  line L189 (0.7421, 3.1) -> (1.3507, 3.1) projected
  line L190 (1.3507, 3.1) -> (1.4767, 3.1) projected
  line L191 (1.4767, 3.1) -> (1.4941, 3.1) projected
  line L192 (1.4941, 3.1) -> (2.5218, 3.1) projected
  line L193 (2.8064, -3.1) -> (2.6318, -3.1) projected
  line L194 (2.6318, -3.1) -> (2.5218, -3.1) projected
  line L195 (2.5218, -3.1) -> (1.4941, -3.1) projected
  line L196 (1.4941, -3.1) -> (1.4767, -3.1) projected
  line L197 (1.4767, -3.1) -> (1.3507, -3.1) projected
  line L198 (1.3507, -3.1) -> (0.7421, -3.1) projected
  line L199 (0.7421, -3.1) -> (0.5889, -3.1) projected
  line L200 (0.5889, -3.1) -> (0.5239, -3.1) projected
  line L201 (0.5239, -3.1) -> (-0.5239, -3.1) projected
  line L202 (-0.5239, -3.1) -> (-0.5889, -3.1) projected
  line L203 (-0.5889, -3.1) -> (-0.7421, -3.1) projected
  line L204 (-0.7421, -3.1) -> (-1.3507, -3.1) projected
  line L205 (-1.3507, -3.1) -> (-1.4767, -3.1) projected
  line L206 (-1.4767, -3.1) -> (-1.4941, -3.1) projected
  line L207 (-1.4941, -3.1) -> (-2.5218, -3.1) projected
  line L208 (-2.5218, -3.1) -> (-2.6318, -3.1) projected
  line L209 (-2.6318, -3.1) -> (-2.8064, -3.1) projected
  line L210 (-2.8064, -3.1) -> (-3.3916, -3.1) projected
  line L211 (-3.3916, -3.1) -> (-3.4855, -3.1) projected
  line L212 (-3.4855, -3.1) -> (-3.4546, -3.1) projected
  line L213 (-3.4546, -3.1) -> (-4.4227, -3.1) projected
  line L214 (-4.4227, -3.1) -> (-4.5736, -3.1) projected
  line L215 (-4.5736, -3.1) -> (-4.7628, -3.1) projected
  line L216 (-4.7628, -3.1) -> (-5.3021, -3.1) projected
  line L217 (-5.3021, -3.1) -> (-5.3604, -3.1) projected
  line L218 (-5.3604, -3.1) -> (-5.2824, -3.1) projected
  line L219 (-5.2824, -3.1) -> (-6.1537, -3.1) projected
  line L220 (-6.1537, -3.1) -> (-6.3397, -3.1) projected
  line L221 (-6.3397, -3.1) -> (-6.5362, -3.1) projected
  line L222 (-6.5362, -3.1) -> (-7.0089, -3.1) projected
  line L223 (-7.0089, -3.1) -> (-7.0293, -3.1) projected
  line L224 (-7.0293, -3.1) -> (-6.9073, -3.1) projected
  line L225 (-6.9073, -3.1) -> (-7.6482, -3.1) projected
  line L226 (-7.6482, -3.1) -> (-7.8621, -3.1) projected
  line L227 (-7.8621, -3.1) -> (-8.0584, -3.1) projected
  line L228 (-8.0584, -3.1) -> (-8.4463, -3.1) projected
  line L229 (-8.4463, -3.1) -> (-8.428, -3.1) projected
  line L230 (-8.428, -3.1) -> (-8.2666, -3.1) projected
  line L231 (-8.2666, -3.1) -> (-8.8488, -3.1) projected
  line L232 (-8.8488, -3.1) -> (-9.0823, -3.1) projected
  line L233 (-9.0823, -3.1) -> (-9.2709, -3.1) projected
  line L234 (-9.2709, -3.1) -> (-9.5592, -3.1) projected
  line L235 (-9.5592, -3.1) -> (-9.5029, -3.1) projected
  line L236 (-9.5029, -3.1) -> (-9.3083, -3.1) projected
  line L237 (-9.3083, -3.1) -> (-9.7093, -3.1) projected
  line L238 (-9.7093, -3.1) -> (-9.9536, -3.1) projected
  line L239 (-9.9536, -3.1) -> (-10.1272, -3.1) projected
  line L240 (-10.1272, -3.1) -> (-10.3047, -3.1) projected
  line L241 (-10.3047, -3.1) -> (-10.2126, -3.1) projected
  line L242 (-10.2126, -3.1) -> (-9.9923, -3.1) projected
  line L243 (-9.9923, -3.1) -> (-10.1967, -3.1) projected
  line L244 (-10.1967, -3.1) -> (-10.4423, -3.1) projected
  line L245 (-10.4423, -3.1) -> (-10.5942, -3.1) projected
  line L246 (-10.5942, -3.1) -> (-10.6542, -3.1) projected
  line L247 (-10.6542, -3.1) -> (-10.5298, -3.1) projected
  line L248 (-10.5298, -3.1) -> (-10.2923, -3.1) projected
  line L249 (-10.2923, -3.1) -> (-10.2923, -3.1) projected
  line L250 (-10.2923, -3.1) -> (-10.5298, -3.1) projected
  line L251 (-10.5298, -3.1) -> (-10.6542, -3.1) projected
  line L252 (-10.6542, -3.1) -> (-10.5942, -3.1) projected
  line L253 (-10.5942, -3.1) -> (-10.4423, -3.1) projected
  line L254 (-10.4423, -3.1) -> (-10.1967, -3.1) projected
  line L255 (-10.1967, -3.1) -> (-9.9923, -3.1) projected
  line L256 (-9.9923, -3.1) -> (-10.2126, -3.1) projected
  line L257 (-10.2126, -3.1) -> (-10.3047, -3.1) projected
  line L258 (-10.3047, -3.1) -> (-10.1272, -3.1) projected
  line L259 (-10.1272, -3.1) -> (-9.9536, -3.1) projected
  line L260 (-9.9536, -3.1) -> (-9.7093, -3.1) projected
  line L261 (-9.7093, -3.1) -> (-9.3083, -3.1) projected
  line L262 (-9.3083, -3.1) -> (-9.5029, -3.1) projected
  line L263 (-9.5029, -3.1) -> (-9.5592, -3.1) projected
  line L264 (-9.5592, -3.1) -> (-9.2709, -3.1) projected
  line L265 (-9.2709, -3.1) -> (-9.0823, -3.1) projected
  line L266 (-9.0823, -3.1) -> (-8.8488, -3.1) projected
  line L267 (-8.8488, -3.1) -> (-8.2666, -3.1) projected
  line L268 (-8.2666, -3.1) -> (-8.428, -3.1) projected
  line L269 (-8.428, -3.1) -> (-8.4463, -3.1) projected
  line L270 (-8.4463, -3.1) -> (-8.0584, -3.1) projected
  line L271 (-8.0584, -3.1) -> (-7.8621, -3.1) projected
  line L272 (-7.8621, -3.1) -> (-7.6482, -3.1) projected
  line L273 (-7.6482, -3.1) -> (-6.9073, -3.1) projected
  line L274 (-6.9073, -3.1) -> (-7.0293, -3.1) projected
  line L275 (-7.0293, -3.1) -> (-7.0089, -3.1) projected
  line L276 (-7.0089, -3.1) -> (-6.5362, -3.1) projected
  line L277 (-6.5362, -3.1) -> (-6.3397, -3.1) projected
  line L278 (-6.3397, -3.1) -> (-6.1537, -3.1) projected
  line L279 (-6.1537, -3.1) -> (-5.2824, -3.1) projected
  line L280 (-5.2824, -3.1) -> (-5.3604, -3.1) projected
  line L281 (-5.3604, -3.1) -> (-5.3021, -3.1) projected
  line L282 (-5.3021, -3.1) -> (-4.7628, -3.1) projected
  line L283 (-4.7628, -3.1) -> (-4.5736, -3.1) projected
  line L284 (-4.5736, -3.1) -> (-4.4227, -3.1) projected
  line L285 (-4.4227, -3.1) -> (-3.4546, -3.1) projected
  line L286 (-3.4546, -3.1) -> (-3.4855, -3.1) projected
  line L287 (-3.4855, -3.1) -> (-3.3916, -3.1) projected
  line L288 (-3.3916, -3.1) -> (-2.8064, -3.1) projected
  line L289 (-2.8064, -3.1) -> (-2.6318, -3.1) projected
  line L290 (-2.6318, -3.1) -> (-2.5218, -3.1) projected
  line L291 (-2.5218, -3.1) -> (-1.4941, -3.1) projected
  line L292 (-1.4941, -3.1) -> (-1.4767, -3.1) projected
  line L293 (-1.4767, -3.1) -> (-1.3507, -3.1) projected
  line L294 (-1.3507, -3.1) -> (-0.7421, -3.1) projected
  line L295 (-0.7421, -3.1) -> (-0.5889, -3.1) projected
  line L296 (-0.5889, -3.1) -> (-0.5239, -3.1) projected
  line L297 (-0.5239, -3.1) -> (0.5239, -3.1) projected
  line L298 (0.5239, -3.1) -> (0.5889, -3.1) projected
  line L299 (0.5889, -3.1) -> (0.7421, -3.1) projected
  line L300 (0.7421, -3.1) -> (1.3507, -3.1) projected
  line L301 (1.3507, -3.1) -> (1.4767, -3.1) projected
  line L302 (1.4767, -3.1) -> (1.4941, -3.1) projected
  line L303 (1.4941, -3.1) -> (2.5218, -3.1) projected
  line L304 (2.5218, -3.1) -> (2.6318, -3.1) projected
  line L305 (2.6318, -3.1) -> (2.8064, -3.1) projected
  line L306 (2.8064, -3.1) -> (3.3916, -3.1) projected
  line L307 (3.3916, -3.1) -> (3.4855, -3.1) projected
  line L308 (3.4855, -3.1) -> (3.4546, -3.1) projected
  line L309 (3.4546, -3.1) -> (4.4227, -3.1) projected
  line L310 (4.4227, -3.1) -> (4.5736, -3.1) projected
  line L311 (4.5736, -3.1) -> (4.7628, -3.1) projected
  line L312 (4.7628, -3.1) -> (5.3021, -3.1) projected
  line L313 (5.3021, -3.1) -> (5.3604, -3.1) projected
  line L314 (5.3604, -3.1) -> (5.2824, -3.1) projected
  line L315 (5.2824, -3.1) -> (6.1537, -3.1) projected
  line L316 (6.1537, -3.1) -> (6.3397, -3.1) projected
  line L317 (6.3397, -3.1) -> (6.5362, -3.1) projected
  line L318 (6.5362, -3.1) -> (7.0089, -3.1) projected
  line L319 (7.0089, -3.1) -> (7.0293, -3.1) projected
  line L320 (7.0293, -3.1) -> (6.9073, -3.1) projected
  line L321 (6.9073, -3.1) -> (7.6482, -3.1) projected
  line L322 (7.6482, -3.1) -> (7.8621, -3.1) projected
  line L323 (7.8621, -3.1) -> (8.0584, -3.1) projected
  line L324 (8.0584, -3.1) -> (8.4463, -3.1) projected
  line L325 (8.4463, -3.1) -> (8.428, -3.1) projected
  line L326 (8.428, -3.1) -> (8.2666, -3.1) projected
  line L327 (8.2666, -3.1) -> (8.8488, -3.1) projected
  line L328 (8.8488, -3.1) -> (9.0823, -3.1) projected
  line L329 (9.0823, -3.1) -> (9.2709, -3.1) projected
  line L330 (9.2709, -3.1) -> (9.5592, -3.1) projected
  line L331 (9.5592, -3.1) -> (9.5029, -3.1) projected
  line L332 (9.5029, -3.1) -> (9.3083, -3.1) projected
  line L333 (9.3083, -3.1) -> (9.7093, -3.1) projected
  line L334 (9.7093, -3.1) -> (9.9536, -3.1) projected
  line L335 (9.9536, -3.1) -> (10.1272, -3.1) projected
  line L336 (10.1272, -3.1) -> (10.3047, -3.1) projected
  line L337 (10.3047, -3.1) -> (10.2126, -3.1) projected
  line L338 (10.2126, -3.1) -> (9.9923, -3.1) projected
  line L339 (9.9923, -3.1) -> (10.1967, -3.1) projected
  line L340 (10.1967, -3.1) -> (10.4423, -3.1) projected
  line L341 (10.4423, -3.1) -> (10.5942, -3.1) projected
  line L342 (10.5942, -3.1) -> (10.6542, -3.1) projected
  line L343 (10.6542, -3.1) -> (10.5298, -3.1) projected
  line L344 (10.5298, -3.1) -> (10.2923, -3.1) projected
  line L345 (10.2923, -3.1) -> (10.2923, -3.1) projected
  line L346 (10.2923, -3.1) -> (10.5298, -3.1) projected
  line L347 (10.5298, -3.1) -> (10.6542, -3.1) projected
  line L348 (10.6542, -3.1) -> (10.5942, -3.1) projected
  line L349 (10.5942, -3.1) -> (10.4423, -3.1) projected
  line L350 (10.4423, -3.1) -> (10.1967, -3.1) projected
  line L351 (10.1967, -3.1) -> (9.9923, -3.1) projected
  line L352 (9.9923, -3.1) -> (10.2126, -3.1) projected
  line L353 (10.2126, -3.1) -> (10.3047, -3.1) projected
  line L354 (10.3047, -3.1) -> (10.1272, -3.1) projected
  line L355 (10.1272, -3.1) -> (9.9536, -3.1) projected
  line L356 (9.9536, -3.1) -> (9.7093, -3.1) projected
  line L357 (9.7093, -3.1) -> (9.3083, -3.1) projected
  line L358 (9.3083, -3.1) -> (9.5029, -3.1) projected
  line L359 (9.5029, -3.1) -> (9.5592, -3.1) projected
  line L360 (9.5592, -3.1) -> (9.2709, -3.1) projected
  line L361 (9.2709, -3.1) -> (9.0823, -3.1) projected
  line L362 (9.0823, -3.1) -> (8.8488, -3.1) projected
  line L363 (8.8488, -3.1) -> (8.2666, -3.1) projected
  line L364 (8.2666, -3.1) -> (8.428, -3.1) projected
  line L365 (8.428, -3.1) -> (8.4463, -3.1) projected
  line L366 (8.4463, -3.1) -> (8.0584, -3.1) projected
  line L367 (8.0584, -3.1) -> (7.8621, -3.1) projected
  line L368 (7.8621, -3.1) -> (7.6482, -3.1) projected
  line L369 (7.6482, -3.1) -> (6.9073, -3.1) projected
  line L370 (6.9073, -3.1) -> (7.0293, -3.1) projected
  line L371 (7.0293, -3.1) -> (7.0089, -3.1) projected
  line L372 (7.0089, -3.1) -> (6.5362, -3.1) projected
  line L373 (6.5362, -3.1) -> (6.3397, -3.1) projected
  line L374 (6.3397, -3.1) -> (6.1537, -3.1) projected
  line L375 (6.1537, -3.1) -> (5.2824, -3.1) projected
  line L376 (5.2824, -3.1) -> (5.3604, -3.1) projected
  line L377 (5.3604, -3.1) -> (5.3021, -3.1) projected
  line L378 (5.3021, -3.1) -> (4.7628, -3.1) projected
  line L379 (4.7628, -3.1) -> (4.5736, -3.1) projected
  line L380 (4.5736, -3.1) -> (4.4227, -3.1) projected
  line L381 (4.4227, -3.1) -> (3.4546, -3.1) projected
  line L382 (3.4546, -3.1) -> (3.4855, -3.1) projected
  line L383 (3.4855, -3.1) -> (3.3916, -3.1) projected
  line L384 (3.3916, -3.1) -> (2.8064, -3.1) projected
  line L385 (-10.68, -3.1) -> (0, -3.1)
  line L386 (-10.68, -3.1) -> (-12.6817, -5.1017)
  line L387 (-12.6817, 3.1) -> (-12.6817, 4.1) projected
  line L388 (-12.6817, -5.1017) -> (0, -5.1017)
  line L389 (0, -5.1017) -> (0, -3.1)
  line L390 (0, -6.942) -> (0, 5.9403) projected
  point P0 (0, 0)
  point P1 (-12.6817, 3.6)
  dimension "d31" = 10.68
  dimension "d32" = 12.6817
  dimension "d33" = 12.6817
  dimension "d34" = 135
  constraints: 8 end point, 3 midpoint, 2 horizontal, 1 perpendicular
  measures "d31" distance of L385.end L385.start
  measures "d32" horizontal distance of L386.end L389.end
  measures "d33" horizontal distance of L389.end point (-12.682, 3.6)
  measures "d34" angle of L225 L386
revolve "Umdrehung1" add sketch "Skizze5" angle 360 about axis through (0, 0, -10) along (0, 0, 1)
equation "\"d10\" = d8"
